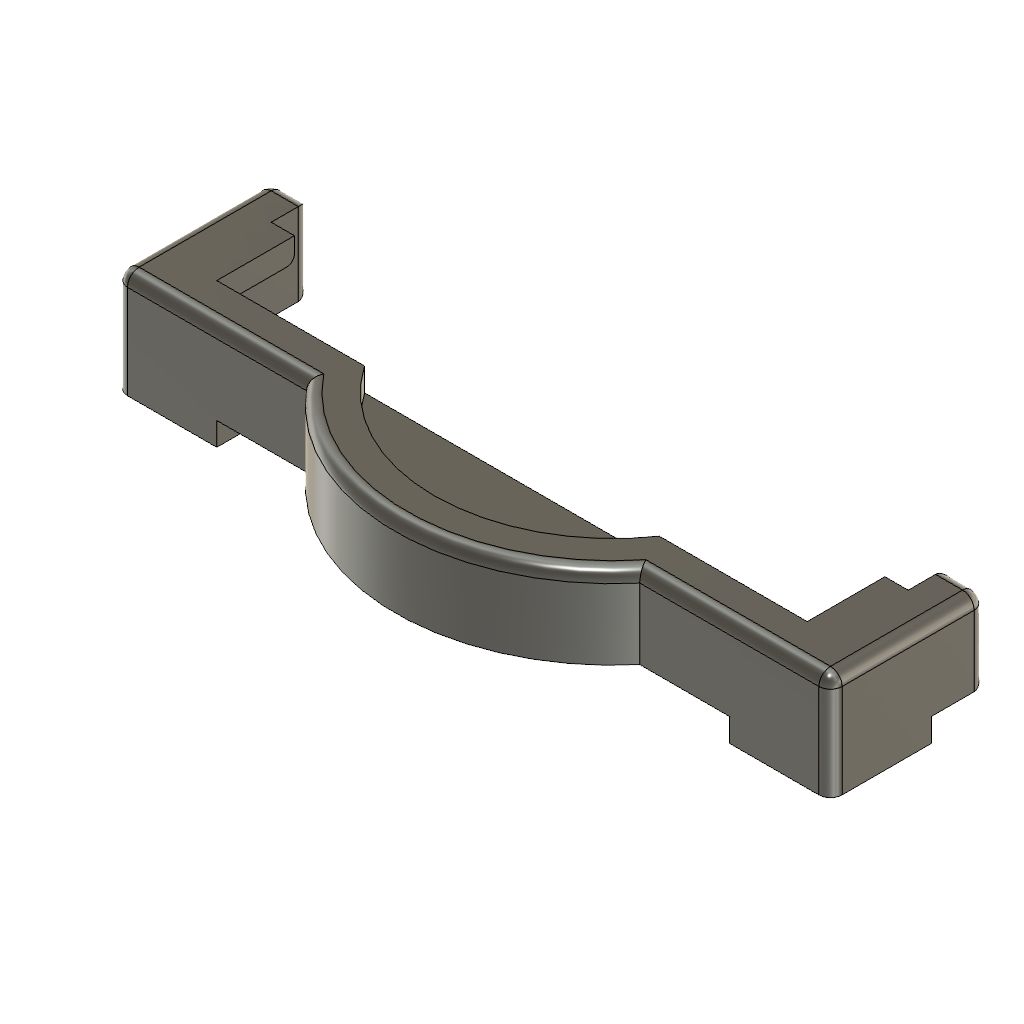
Lens cover holder (Autodesk Fusion 360 design; units mm, degrees)
Autodesk Fusion 360 part; units mm, degrees
sketch "Sketch1" plane through (0, 0, 0) normal (0, 0, 1) x (1, 0, 0)
  circle A0 centre (0, 0) radius 23
  line L0 (41, 16) -> (-41, 16)
  line L1 (-41, 16) -> (-41, -16)
  line L2 (41, -16) -> (41, 16)
  line L3 (41, 16) -> (-41, -16) construction
  line L4 (-41, 16) -> (41, -16) construction
  line L5 (41, -13) -> (-41, -13)
  dimension "d1" = 46
  dimension "d2" = 82
  dimension "d3" = 32
  dimension "d4" = 3
  constraint coincident A0.centre origin
  constraint horizontal L0
  constraint perpendicular L0 L1
  constraint parallel L1 L2
  constraint coincident L3 A0.centre
  constraint coincident L4 A0.centre
  constraint horizontal L5
  measures "d1" diameter of A0
  measures "d2" distance of L1.end L2.start
  measures "d3" distance of L0.end L1.end
  measures "d4" distance of L1.end L5.end
sketch "Sketch2" plane through (0, 0, 0) normal (0, 0, 1) x (1, 0, 0)
  line L0 (41, -13) -> (18.9737, -13)
  line L1 (-18.9737, -13) -> (-41, -13)
  arc A0 (-18.9737, -13) -> (18.9737, -13) centre (0, 0) ccw
  line L2 (41, -18) -> (21.4476, -18)
  arc A1 (-21.4476, -18) -> (21.4476, -18) centre (0, 0) ccw
  line L3 (-21.4476, -18) -> (-41, -18)
  line L4 (41, -13) -> (41, -18)
  line L5 (-41, -13) -> (-41, -18)
  line L6 (-41, -13) -> (-46, -13)
  line L7 (-46, -13) -> (-46, -18)
  line L8 (-46, -18) -> (-41, -18)
  line L9 (-41, -18) -> (-41, -13)
  line L10 (41, -13) -> (46, -13)
  line L11 (46, -13) -> (46, -18)
  line L12 (46, -18) -> (41, -18)
  line L13 (41, -18) -> (41, -13)
  point P0 (41, -13)
  dimension "d5" = 5
  dimension "d6" = 5
  dimension "d7" = 5
  constraint coincident P0 L0.start
  constraint perpendicular L2 L4
  constraint perpendicular L3 L5
  constraint horizontal L6
  constraint vertical L7
  constraint horizontal L8
  constraint vertical L9
  constraint horizontal L10
  constraint vertical L11
  constraint horizontal L12
  constraint vertical L13
  measures "d6" distance of L1.end L6.end
  measures "d7" distance of P0 L10.end
extrude "Extrude1" add sketch "Sketch2" along normal blind 10.5 makes body 1
sketch "Sketch3" plane through (0, -13, 0) normal (0, 1, 0) x (-1, 0, 0)
  line L0 (-46, 0) -> (-18.9737, 0)
  line L1 (-18.9737, 0) -> (-18.9737, 10.5)
  line L2 (-18.9737, 10.5) -> (-46, 10.5)
  line L3 (-46, 10.5) -> (-46, 0)
  line L4 (-46, 0) -> (-41, 0)
  line L5 (-41, 0) -> (-41, 10.5)
  line L6 (-41, 10.5) -> (-46, 10.5)
  line L7 (-46, 10.5) -> (-46, 0)
  line L8 (46, 0) -> (41, 0)
  line L9 (41, 0) -> (41, 10.5)
  line L10 (41, 10.5) -> (46, 10.5)
  line L11 (46, 10.5) -> (46, 0)
  line L12 (-41, 10.5) -> (-38, 10.5)
  line L13 (-38, 10.5) -> (-38, 0)
  line L14 (-38, 0) -> (-41, 0)
  line L15 (-41, 0) -> (-41, 10.5)
  line L16 (41, 10.5) -> (38, 10.5)
  line L17 (38, 10.5) -> (38, 0)
  line L18 (38, 0) -> (41, 0)
  line L19 (41, 0) -> (41, 10.5)
  line L20 (-41, 10.5) -> (-38, 10.5)
  line L21 (-38, 10.5) -> (-38, 7.5)
  line L22 (-38, 7.5) -> (-41, 7.5)
  line L23 (-41, 7.5) -> (-41, 10.5)
  line L24 (38, 10.5) -> (41, 10.5)
  line L25 (41, 10.5) -> (41, 7.5)
  line L26 (41, 7.5) -> (38, 7.5)
  line L27 (38, 7.5) -> (38, 10.5)
  point P0 (46, 0)
  dimension "d10" = 5
  dimension "d11" = 5
  dimension "d14" = 3
  dimension "d15" = 3
  dimension "d16" = 3
  dimension "d17" = 3
  constraint horizontal L4
  constraint vertical L5
  constraint horizontal L6
  constraint vertical L7
  constraint coincident L0.start L3.end
  constraint horizontal L8
  constraint vertical L9
  constraint horizontal L10
  constraint vertical L11
  constraint coincident P0 L8.start
  constraint horizontal L12
  constraint vertical L13
  constraint horizontal L14
  constraint vertical L15
  constraint horizontal L16
  constraint vertical L17
  constraint horizontal L18
  constraint vertical L19
  constraint horizontal L20
  constraint vertical L21
  constraint horizontal L22
  constraint vertical L23
  constraint horizontal L24
  constraint vertical L25
  constraint horizontal L26
  constraint vertical L27
  measures "d10" distance of L0.start L4.end
  measures "d11" distance of P0 L8.end
  measures "d14" distance of L5.end L12.end
  measures "d15" distance of L9.end L16.end
  measures "d16" distance of L5.end L22.end
  measures "d17" distance of L16.end L26.end
extrude "Extrude2" add sketch "Sketch3" along normal blind 15 contours L0 L2 L3 L4 L5 L6 L7 L15 L23 | L8 L9 L10 L11 L19 L25 bodies 1
extrude "Extrude3" add sketch "Sketch3" along normal blind 10 contours L2 L5 L12 L13 L15 L20 L21 L22 L23 | L9 L16 L17 L19 L24 L25 L26 L27 bodies 1
sketch "Sketch4" plane through (0, -13, 0) normal (0, 1, 0) x (-1, 0, 0)
  line L0 (41, 7.5) -> (38, 7.5)
  line L1 (38, 7.5) -> (38, 10.5)
  line L2 (38, 10.5) -> (18.9737, 10.5)
  line L3 (18.9737, 10.5) -> (18.9737, 0)
  line L4 (18.9737, 0) -> (41, 0)
  line L5 (41, 0) -> (41, 7.5)
  line L6 (41, 0) -> (-41, 0)
  line L7 (-41, 0) -> (-41, 3)
  line L8 (-41, 3) -> (41, 3)
  line L9 (41, 3) -> (41, 0)
  line L10 (38, 7.5) -> (-38, 7.5)
  line L11 (-38, 7.5) -> (-38, 4.5)
  line L12 (-38, 4.5) -> (38, 4.5)
  line L13 (38, 4.5) -> (38, 7.5)
  line L14 (38, 7.5) -> (35, 7.5)
  line L15 (35, 7.5) -> (35, 4.5)
  line L16 (35, 4.5) -> (38, 4.5)
  line L17 (38, 4.5) -> (38, 7.5)
  line L18 (-38, 7.5) -> (-35, 7.5)
  line L19 (-35, 7.5) -> (-35, 4.5)
  line L20 (-35, 4.5) -> (-38, 4.5)
  line L21 (-38, 4.5) -> (-38, 7.5)
  dimension "d20" = 3
  dimension "d21" = 3
  dimension "d22" = 3
  dimension "d23" = 3
  constraint horizontal L6
  constraint vertical L7
  constraint horizontal L8
  constraint vertical L9
  constraint coincident L4.end L5.start
  constraint horizontal L10
  constraint vertical L11
  constraint horizontal L12
  constraint vertical L13
  constraint coincident L0.end L1.start
  constraint horizontal L14
  constraint vertical L15
  constraint horizontal L16
  constraint vertical L17
  constraint horizontal L18
  constraint vertical L19
  constraint horizontal L20
  constraint vertical L21
  measures "d20" distance of L4.end L8.end
  measures "d21" distance of L0.end L12.end
  measures "d22" distance of L0.end L14.end
  measures "d23" distance of L10.end L18.end
extrude "Extrude4" add sketch "Sketch4" along normal blind 3 separate body contours L10 L12 L13 L14 L15 L16 L17 | L10 L11 L12 L18 L19 L20 L21 makes body 2 at (-38, -12, 5.5) makes body 3 at (35, -12, 6.5)
sketch "Sketch5" plane through (0, 0, 7.5) normal (0, 0, 1) x (-1, 0, 0)
  line L0 (-35, 13) -> (-38, 13)
  line L1 (-38, 13) -> (-38, 10)
  line L2 (-38, 10) -> (-35, 10)
  line L3 (-35, 10) -> (-35, 13)
  line L4 (-35, 10) -> (35, 10)
  line L5 (-35, 10) -> (-35, 13)
  line L6 (-18.9737, 13) -> (-35, 13)
  line L7 (35, 10) -> (35, 13)
  line L8 (35, 13) -> (18.9737, 13)
  arc A0 (18.9737, 13) -> (-18.9737, 13) centre (0, 0) ccw
  line L9 (-18.9737, 13) -> (18.9737, 13)
  point P0 (35, 10)
  point P1 (-18.9737, 13)
  point P2 (35, 13)
  point P3 (18.9737, 13)
  constraint coincident L2.end L3.start
  constraint coincident P0 L4.end
  constraint coincident L0.start L3.end
  constraint coincident P1 L6.start
  constraint coincident P2 L7.end
  constraint coincident P3 L8.end
extrude "Extrude5" add sketch "Sketch5" against normal blind 3 contours A0 L9 bodies 1
extrude "Extrude6" add 1 faces at (-44.3333, -9.6667, 0) along direction (0, 0, -1) blind 0.1 on bodies 1 bodies 1
sketch "Sketch6" plane through (0, 0, -0.1) normal (0, 0, -1) x (1, 0, 0)
  line L0 (46, -2) -> (46, 18)
  line L1 (46, 18) -> (21.4476, 18)
  arc A0 (21.4476, 18) -> (-21.4476, 18) centre (0, 0) ccw
  line L2 (-21.4476, 18) -> (-46, 18)
  line L3 (-46, 18) -> (-46, -2)
  line L4 (-46, -2) -> (-41, -2)
  line L5 (-41, -2) -> (-41, 13)
  line L6 (-41, 13) -> (-18.9737, 13)
  arc A1 (18.9737, 13) -> (-18.9737, 13) centre (0, 0) ccw
  line L7 (18.9737, 13) -> (41, 13)
  line L8 (41, 13) -> (41, -2)
  line L9 (41, -2) -> (46, -2)
  line L10 (46, 18) -> (33, 18)
  line L11 (33, 18) -> (33, 5)
  line L12 (33, 5) -> (46, 5)
  line L13 (46, 5) -> (46, 18)
  line L14 (-46, 18) -> (-33, 18)
  line L15 (-33, 18) -> (-33, 5)
  line L16 (-33, 5) -> (-46, 5)
  line L17 (-46, 5) -> (-46, 18)
  dimension "d30" = 13
  dimension "d31" = 13
  dimension "d32" = 13
  dimension "d33" = 13
  constraint horizontal L10
  constraint vertical L11
  constraint horizontal L12
  constraint vertical L13
  constraint coincident L0.end L1.start
  constraint horizontal L14
  constraint vertical L15
  constraint horizontal L16
  constraint vertical L17
  constraint coincident L2.end L3.start
  measures "d30" distance of L0.end L10.end
  measures "d31" distance of L0.end L12.end
  measures "d32" distance of L2.end L14.end
  measures "d33" distance of L2.end L16.end
extrude "Extrude7" add sketch "Sketch6" along normal blind 3 contours L0 L1 L7 L8 L10 L11 L12 L13 | L7 L8 L11 L12 | L2 L3 L5 L6 L14 L15 L16 L17 | L5 L6 L15 L16 bodies 1
fillet "Fillet1" radius 1 4 edges at (-37, -5, -0.1) (-39.5, -3, 7.5) (39.5, -3, 7.5) (37, -5, -0.1) on bodies 1
fillet "Fillet2" radius 1.5 15 edges at (43.5, 2, 10.5) (41, 2, 5.2) (46, 2, 5.2) (43.5, 2, -0.1) (46, -8, 10.5) (33.7238, -18, 10.5) (0, -28, 10.5) (-33.7238, -18, 10.5) (-46, -8, 10.5) (-46, 2, 5.2) (-41, 2, 5.2) (-43.5, 2, 10.5) (-43.5, 2, -0.1) (-46, -18, 3.7) (46, -18, 3.7) on bodies 1
